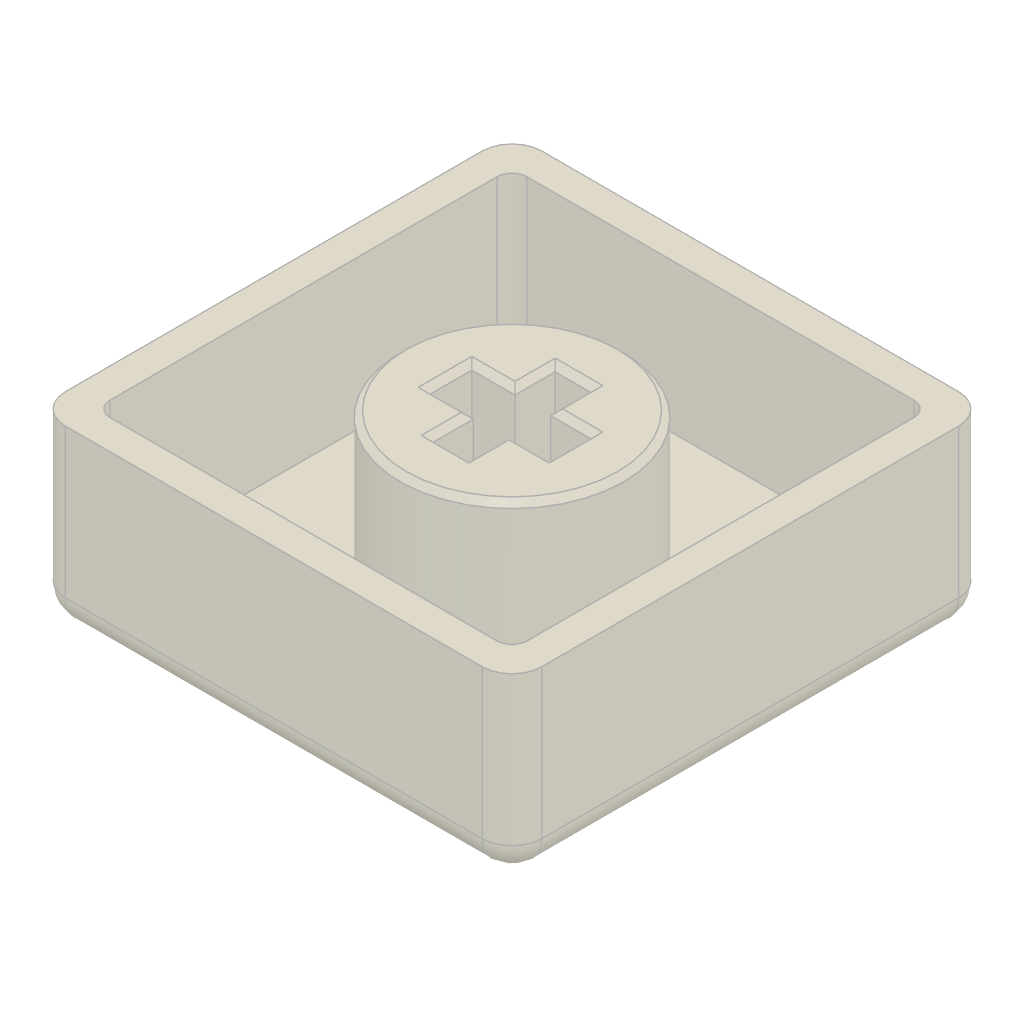
keycaps (Autodesk Fusion 360 design; units mm, degrees)
part number: 2026-10-06-00-52-50-519
Autodesk Fusion 360 part; units mm, degrees
sketch "Sketch1" plane through (0, 0, 0) normal (0, 1, 0) x (1, 0, 0)
  line L0 (0, 0) -> (16, 0)
  line L1 (16, 0) -> (16, 16)
  line L2 (16, 16) -> (0, 16)
  line L3 (0, 16) -> (0, 0)
  dimension "d1" = 16
  dimension "d2" = 16
  constraint horizontal L0
  constraint vertical L1
  constraint horizontal L2
  constraint vertical L3
  constraint coincident L0.start L3.end
  measures "d1" distance of L0.start L0.end
  measures "d2" distance of L0.start L2.end
extrude "Extrude1" add sketch "Sketch1" along normal blind 1
sketch "Sketch2" plane through (0, 1, 0) normal (0, 1, 0) x (-1, 0, 0)
  line L0 (0, -16) -> (0, 0)
  line L1 (0, 0) -> (-16, 0)
  line L2 (-16, 0) -> (-16, -16)
  line L3 (-16, -16) -> (0, -16)
  line L4 (-7.45, -10) -> (-8.65, -10)
  line L5 (-8.65, -10) -> (-8.65, -8.65)
  line L6 (-8.65, -8.65) -> (-10, -8.65)
  line L7 (-10, -8.65) -> (-10, -7.25)
  line L8 (-10, -7.25) -> (-8.65, -7.25)
  line L9 (-8.65, -7.25) -> (-8.65, -5.9)
  line L10 (-8.65, -5.9) -> (-7.45, -5.9)
  line L11 (-7.45, -5.9) -> (-7.45, -7.25)
  line L12 (-7.45, -7.25) -> (-6, -7.25)
  line L13 (-6, -7.25) -> (-6, -8.65)
  line L14 (-6, -8.65) -> (-7.45, -8.65)
  line L15 (-7.45, -8.65) -> (-7.45, -10)
  line L16 (-7.45, -8.65) -> (-8.65, -7.25) construction
  line L17 (-8.65, -8.65) -> (-7.45, -7.25) construction
  circle A0 centre (-8.05, -7.95) radius 3.75
  dimension "d5" = 4
  dimension "d6" = 1.45
  dimension "d7" = 1.35
  dimension "d8" = 1.4
  dimension "d9" = 1.2
  dimension "d10" = 1.35
  dimension "d11" = 6
  dimension "d12" = 5.9
  dimension "d13" = 6
  dimension "d14" = 6
  dimension "d15" = 7.5
  dimension "d27" = 16
  constraint horizontal L4
  constraint perpendicular L4 L5
  constraint perpendicular L5 L6
  constraint vertical L7
  constraint perpendicular L7 L8
  constraint perpendicular L8 L9
  constraint perpendicular L7 L10
  constraint perpendicular L10 L11
  constraint perpendicular L11 L12
  constraint perpendicular L12 L13
  constraint perpendicular L11 L14
  constraint vertical L15
  constraint collinear L11 L15
  constraint collinear L5 L9
  constraint collinear L8 L12
  constraint collinear L6 L14
  constraint midpoint L17 A0.centre
  measures "d5" distance of L7 L13
  measures "d6" distance of L13.end L14.end
  measures "d7" distance of L4.start L14.end
  measures "d8" distance of L12.end L13.end
  measures "d9" distance of L4.start L4.end
  measures "d10" distance of L10.end L11.end
  measures "d11" distance of L3 L4
  measures "d12" distance of L1 L10
  measures "d13" distance of L2 L7
  measures "d14" distance of L0 L13
  measures "d15" diameter of A0
  measures "d27" distance of L0 L2
extrude "Extrude2" add sketch "Sketch2" along normal blind 5 contours A0
sketch "Sketch3" plane through (0, 1, 0) normal (0, 1, 0) x (-1, 0, 0)
  line L0 (0, -16) -> (0, 0)
  line L1 (0, 0) -> (-16, 0)
  line L2 (-16, 0) -> (-16, -16)
  line L3 (-16, -16) -> (0, -16)
  circle A0 centre (-8.05, -7.95) radius 3.75
  line L4 (0, -16) -> (-16, -16)
  line L5 (-16, -16) -> (-16, 0)
  line L6 (-16, 0) -> (0, 0)
  line L7 (0, 0) -> (0, -16)
  line L8 (-15, -1) -> (-1, -1)
  line L9 (-1, -1) -> (-1, -15)
  line L10 (-1, -15) -> (-15, -15)
  line L11 (-15, -15) -> (-15, -1)
  dimension "d18" = 1
  constraint horizontal L4
  constraint vertical L5
  constraint horizontal L6
  constraint vertical L7
  constraint coincident L1.end L2.start
  constraint coincident L0.start L3.end
extrude "Extrude3" add sketch "Sketch3" along normal blind 5 contours L0 L1 L2 L3 L4 L5 L6 L7
chamfer "Chamfer1" distance 0.2 angle 45 12 edges at (7.45, 6, -9.325) (8.05, 6, -10) (8.65, 6, -9.325) (9.325, 6, -8.65) (10, 6, -7.95) (9.325, 6, -7.25) (8.65, 6, -6.575) (8.05, 6, -5.9) (7.45, 6, -6.575) (6.725, 6, -7.25) (6, 6, -7.95) (6.725, 6, -8.65) tangent chain off
chamfer "Chamfer1" distance 0.2 angle 45 1 edges at (11.5462, 6, -9.3061) tangent chain off
fillet "Fillet1" radius 1 4 edges at (0, 3, -16) (0, 3, 0) (16, 3, 0) (16, 3, -16) 1 faces at (5.3333, 0, -5.3333)
fillet "Fillet1" radius 0.5 4 edges at (1, 3.5, -15) (1, 3.5, -1) (15, 3.5, -1) (15, 3.5, -15)
equation "d10 = d7"
